Autodesk Fusion 360 part; units mm, degrees
(part 2 of 2)
equation "d1675 = ( lt_x + pk_h ) - ( lt_x - pk_h )"
equation "d1676 = ( y_bg + rt_h ) - ( y_bg - rt_h )"
equation "d1677 = abs(lt_x - pk_h)"
equation "d1678 = abs(y_bg - rt_h)"
equation "d1679 = ( shelf_z - 60 mm ) * ( 1 )"
equation "d1680 = ( shelf_z + 40 mm ) - ( shelf_z - 60 mm )"
equation "d1683 = abs(lt_x)"
equation "d1684 = abs(shelf_z)"
equation "d1685 = ( y_bf ) * ( 1 )"
equation "d1686 = ( y_bf + tray_t + felt_t ) - ( y_bf )"
equation "d1688 = ( cut_x1 + tray_t + pk_l ) - ( cut_x1 + tray_t )"
equation "d1689 = ( y_bg + rt_h ) - ( y_bg - rt_h )"
equation "d1690 = abs(cut_x1 + tray_t)"
equation "d1691 = abs(y_bg - rt_h)"
equation "d1692 = ( trunk_z - pk_h ) * ( 1 )"
equation "d1693 = ( trunk_z + pk_h ) - ( trunk_z - pk_h )"
equation "d1695 = ( x_rf - tray_t - grm_c ) - ( cut_x1 + tray_t + pk_l )"
equation "d1696 = ( y_bg + rt_h ) - ( y_bg - rt_h )"
equation "d1697 = abs(cut_x1 + tray_t + pk_l)"
equation "d1698 = abs(y_bg - rt_h)"
equation "d1699 = ( trunk_z - rt_w / 2 ) * ( 1 )"
equation "d1700 = ( trunk_z + rt_w / 2 ) - ( trunk_z - rt_w / 2 )"
equation "d1702 = ( x_rf + tray_t + felt_t ) - ( x_rf )"
equation "d1703 = ( y_bf + 20 mm ) - ( y_bf + 2 mm )"
equation "d1704 = abs(x_rf)"
equation "d1705 = abs(y_bf + 2 mm)"
equation "d1706 = ( trunk_z - 60 mm ) * ( 1 )"
equation "d1707 = ( trunk_z + 60 mm ) - ( trunk_z - 60 mm )"
equation "d1709 = ( x_rg + rt_h ) - ( x_rg - rt_h )"
equation "d1710 = ( y_xc + cs_h ) - ( y_xc + cs_h - pk_l )"
equation "d1711 = abs(x_rg - rt_h)"
equation "d1712 = abs(y_xc + cs_h - pk_l)"
equation "d1713 = ( trunk_z - pk_h ) * ( 1 )"
equation "d1714 = ( trunk_z + pk_h ) - ( trunk_z - pk_h )"
equation "d1716 = ( x_rf ) - ( x_rf - tray_t - grm_c )"
equation "d1717 = ( y_xc + cs_h ) - ( y_xc - cs_h )"
equation "d1718 = abs(x_rf - tray_t - grm_c)"
equation "d1719 = abs(y_xc - cs_h)"
equation "d1720 = ( trunk_z - 40 mm ) * ( 1 )"
equation "d1721 = ( trunk_z + 40 mm ) - ( trunk_z - 40 mm )"
equation "d1723 = ( x_rg + rt_h ) - ( x_rg - rt_h )"
equation "d1724 = ( y_xc + cs_h - pk_l ) - ( y_kit + pk_l / 2 )"
equation "d1725 = abs(x_rg - rt_h)"
equation "d1726 = abs(y_kit + pk_l / 2)"
equation "d1727 = ( trunk_z - rt_w / 2 ) * ( 1 )"
equation "d1728 = ( trunk_z + rt_w / 2 ) - ( trunk_z - rt_w / 2 )"
equation "d1730 = ( x_rg + rt_h ) - ( x_rg - rt_h )"
equation "d1731 = ( y_kit + pk_l / 2 ) - ( y_kit - pk_l / 2 )"
equation "d1732 = abs(x_rg - rt_h)"
equation "d1733 = abs(y_kit - pk_l / 2)"
equation "d1734 = ( trunk_z - rt_w / 2 ) * ( 1 )"
equation "d1735 = ( trunk_z + rt_w / 2 + 120 mm ) - ( trunk_z - rt_w / 2 )"
equation "d1737 = kit_d"
equation "d1738 = abs(y_kit)"
equation "d1739 = abs(trunk_z + 80 mm)"
equation "d1740 = ( x_rf ) * ( 1 )"
equation "d1741 = ( x_rf + tray_t + felt_t ) - ( x_rf )"
equation "d1743 = ( x_rg + rt_h ) - ( x_rg - rt_h )"
equation "d1744 = ( y_kit - pk_l / 2 ) - ( y_cx - grm_d / 2 )"
equation "d1745 = abs(x_rg - rt_h)"
equation "d1746 = abs(y_cx - grm_d / 2)"
equation "d1747 = ( trunk_z - rt_w / 2 ) * ( 1 )"
equation "d1748 = ( trunk_z + rt_w / 2 ) - ( trunk_z - rt_w / 2 )"
equation "d1750 = grm_d"
equation "d1751 = abs(y_cx)"
equation "d1752 = abs(trunk_z)"
equation "d1753 = ( x_rf - ch_off ) * ( 1 )"
equation "d1754 = ( x_rf + tray_t + felt_t ) - ( x_rf - ch_off )"
equation "d1756 = ( x_rf - ch_off ) - ( x_rf - ch_off - ch_w )"
equation "d1757 = ( col_y1 - col_skin ) - ( col_y1 - col_skin - ch_w )"
equation "d1758 = abs(x_rf - ch_off - ch_w)"
equation "d1759 = abs(col_y1 - col_skin - ch_w)"
equation "d1760 = ( trunk_z - grm_d ) * ( 1 )"
equation "d1761 = ( col_z1 - grm_c ) - ( trunk_z - grm_d )"
equation "d1763 = ( x_rf - ch_off ) - ( x_rf - ch_off - ch_w )"
equation "d1764 = ( col_y1 - col_skin - ch_w ) - ( col_y0 + grm_c )"
equation "d1765 = abs(x_rf - ch_off - ch_w)"
equation "d1766 = abs(col_y0 + grm_c)"
equation "d1767 = ( col_z1 - 20 mm ) * ( 1 )"
equation "d1768 = ( col_z1 - 4 mm ) - ( col_z1 - 20 mm )"
equation "d1770 = grm_d"
equation "d1771 = abs(x_rf - ch_off - ch_w / 2)"
equation "d1772 = abs(col_z1 - 12 mm)"
equation "d1773 = ( col_y0 - grm_c ) * ( 1 )"
equation "d1774 = ( col_y0 + grm_c ) - ( col_y0 - grm_c )"
equation "d1776 = ( x_rf - ch_off ) - ( x_rf - ch_off - ch_w )"
equation "d1777 = ( col_y0 - grm_c ) - ( col_y0 - 20 mm )"
equation "d1778 = abs(x_rf - ch_off - ch_w)"
equation "d1779 = abs(col_y0 - 20 mm)"
equation "d1780 = ( col_z1 - 20 mm ) * ( 1 )"
equation "d1781 = ( col_z1 - 4 mm ) - ( col_z1 - 20 mm )"
equation "d1783 = grm_d"
equation "d1784 = abs(x_rf - ch_off - ch_w / 2)"
equation "d1785 = abs(col_y1 - col_skin - ch_w / 2)"
equation "d1786 = ( col_z1 - grm_c ) * ( 1 )"
equation "d1787 = ( col_z1 + grm_c ) - ( col_z1 - grm_c )"
equation "d1789 = ( x_rf - ch_off ) - ( x_rf - ch_off - ch_w )"
equation "d1790 = ( col_y1 - col_skin ) - ( col_y1 - col_skin - ch_w )"
equation "d1791 = abs(x_rf - ch_off - ch_w)"
equation "d1792 = abs(col_y1 - col_skin - ch_w)"
equation "d1793 = ( col_z1 + grm_c ) * ( 1 )"
equation "d1794 = ( col_z1 + 40 mm ) - ( col_z1 + grm_c )"
equation "d1796 = ( hub_x0 + hub_w ) - ( hub_x0 )"
equation "d1797 = ( col_y1 ) - ( col_y1 - hub_rec )"
equation "d1798 = abs(hub_x0)"
equation "d1799 = abs(col_y1 - hub_rec)"
equation "d1800 = ( hub_zc - hub_w / 2 ) * ( 1 )"
equation "d1801 = ( hub_zc + hub_w / 2 ) - ( hub_zc - hub_w / 2 )"
equation "d1803 = grm_s"
equation "d1804 = abs(call_y)"
equation "d1805 = abs(shelf_z)"
equation "d1806 = ( x_rf ) * ( 1 )"
equation "d1807 = ( x_rf + tray_t + felt_t ) - ( x_rf )"
equation "d1809 = ( x_rg + rt_h ) - ( x_rg - rt_h )"
equation "d1810 = ( call_y + pk_h ) - ( call_y - pk_h )"
equation "d1811 = abs(x_rg - rt_h)"
equation "d1812 = abs(call_y - pk_h)"
equation "d1813 = ( shelf_z - grm_s / 2 - pk_l ) * ( 1 )"
equation "d1814 = ( shelf_z - grm_s / 2 ) - ( shelf_z - grm_s / 2 - pk_l )"
equation "d1816 = ( x_rg + rt_h ) - ( x_rg - rt_h )"
equation "d1817 = ( call_y + rt_h ) - ( call_y - rt_h )"
equation "d1818 = abs(x_rg - rt_h)"
equation "d1819 = abs(call_y - rt_h)"
equation "d1820 = ( call_z + grm_s / 2 ) * ( 1 )"
equation "d1821 = ( shelf_z - grm_s / 2 - pk_l ) - ( call_z + grm_s / 2 )"
equation "d1823 = grm_s"
equation "d1824 = abs(call_y)"
equation "d1825 = abs(call_z)"
equation "d1826 = ( x_rf ) * ( 1 )"
equation "d1827 = ( x_rf + tray_t + felt_t ) - ( x_rf )"
equation "d1829 = ( lt_x + dw_h ) - ( lt_x - dw_h )"
equation "d1830 = ( y_bg + dw_h ) - ( y_bg - dw_h )"
equation "d1831 = abs(lt_x - dw_h)"
equation "d1832 = abs(y_bg - dw_h)"
equation "d1833 = ( shelf_z + 40 mm ) * ( 1 )"
equation "d1834 = ( z_cf - 4 mm ) - ( shelf_z + 40 mm )"
equation "d1836 = ( ceil_x + dw_h ) - ( lt_x - dw_h )"
equation "d1837 = ( y_bg + dw_h ) - ( y_bg - dw_h )"
equation "d1838 = abs(lt_x - dw_h)"
equation "d1839 = abs(y_bg - dw_h)"
equation "d1840 = ( z_cf - 4 mm ) * ( 1 )"
equation "d1841 = ( z_cf + 4 mm ) - ( z_cf - 4 mm )"
equation "d1843 = ( ceil_x + dw_h ) - ( ceil_x - dw_h )"
equation "d1844 = ( y_bg + dw_h ) - ( y_bg - dw_h )"
equation "d1845 = abs(ceil_x - dw_h)"
equation "d1846 = abs(y_bg - dw_h)"
equation "d1847 = ( z_cf + 4 mm ) * ( 1 )"
equation "d1848 = ( z_xc + dw_h ) - ( z_cf + 4 mm )"
equation "d1850 = grm_s"
equation "d1851 = abs(ceil_x)"
equation "d1852 = abs(z_xc)"
equation "d1853 = ( y_bf ) * ( 1 )"
equation "d1854 = ( y_bf + tray_t + felt_t ) - ( y_bf )"
equation "d1856 = grm_d"
equation "d1857 = abs(ceil_x)"
equation "d1858 = abs(z_xc)"
equation "d1859 = ( ceil_y1 - tray_t ) * ( 1 )"
equation "d1860 = ( y_bf ) - ( ceil_y1 - tray_t )"
equation "d1862 = ( ceil_x + dw_h ) - ( ceil_x - dw_h )"
equation "d1863 = ( ceil_y1 - tray_t ) - ( ceil_y0 + tray_t )"
equation "d1864 = abs(ceil_x - dw_h)"
equation "d1865 = abs(ceil_y0 + tray_t)"
equation "d1866 = ( z_xc - dw_h ) * ( 1 )"
equation "d1867 = ( z_cg + dw_h ) - ( z_xc - dw_h )"
equation "d1869 = grm_d"
equation "d1870 = abs(ceil_x)"
equation "d1871 = abs(z_cg)"
equation "d1872 = ( soff_y ) * ( 1 )"
equation "d1873 = ( ceil_y0 + tray_t ) - ( soff_y )"
named bodies: "PU POWER UNIT ENVELOPE", "PU-PLATE FRONT PLATE - OVER THE FELT EDGE, 2 MM OFF THE FELT", "INLET MAINS INLET ENVELOPE", "LAN-FT LAN FEED-THROUGH ENVELOPE", "SLEEVE MAINS AND LAN SLEEVE", "P5 POCKET - LIGHT FEED AT THE UNIT", "L1-B2 ROUTE - LIGHT FEED - B2-CASS", "G-B2-B4 GROMMET PAIR - B2/B4 LINING JOINT", "P4 POCKET - LIGHT FEED AT THE B2/B4 JOINT - B4-CASS", "L1-B4 ROUTE - LIGHT FEED - B4-CASS", "P6 POCKET - LIGHT SHELF FEED", "FX-SHELF FELT HOLE - LIGHT SHELF EXIT (FELT ONLY, NO STEEL)", "P1 POCKET - TRUNK AT THE UNIT", "T1-B2 ROUTE - TRUNK - B2-CASS", "FS-CNR FELT SLOT - CORNER - R1-CASS (HIDDEN BEHIND B2-CASS)", "P2 POCKET - TRUNK AT THE BACK-RIGHT CORNER - R1-CASS", "S-CNR GROMMETED SLOT - CORNER - B2-CASS END RETURN", "T1-R1A ROUTE - TRUNK - R1-CASS - CORNER TO KIT", "P3-KIT POCKET - VOICE KIT DROP", "FA-KIT FELT HOLE - VOICE KIT ACCESS (FELT ONLY, NO STEEL)", "T1-R1B ROUTE - TRUNK - R1-CASS - KIT TO COLUMN", "FX-COL FELT HOLE - EXIT INTO THE AIR COLUMN (FELT ONLY, NO STEEL)", "CHASE ROUTE - CABLE CHASE IN THE AIR COLUMN", "TO-DR ROUTE - ACROSS THE COLUMN TOP TO DR", "G-DR BUSHED HOLE - DR BACK PLATE", "IN-DR ROUTE - INSIDE DR TO THE SUPPLY FAN BOX AND INLET SENSOR", "G-SOFFIT BUSHED HOLE - SOFFIT UNDERSIDE CASING", "TO-SOFFIT ROUTE - TO THE EXHAUST FANS IN THE SOFFIT", "HUB SENSOR HUB AND CONTROLS ZONE", "FX-CALL0 FELT HOLE - R2-CASS BEHIND THE SHELF (FELT ONLY, NO STEEL)", "P7 POCKET - CALL LIGHT DROP AT THE SHELF - R2-CASS", "CALL-R2 ROUTE - CALL LIGHT DROP - R2-CASS", "FX-CALL2 FELT HOLE - CALL LIGHT EXIT (FELT ONLY, NO STEEL)", "C1-UP DRAW WIRE - B4-CASS UP", "C1-JOG DRAW WIRE - B4-CASS ALONG X", "C1-RISE DRAW WIRE - B4-CASS TO THE CEILING HOLE", "FX-CEIL FELT HOLE - B4-CASS BELOW ITS TOP LIP (FELT ONLY, NO STEEL)", "G-CEIL-B GROMMET - CEILING CASSETTE BACK RETURN", "C1-CEIL DRAW WIRE - CEILING CASSETTE", "G-CEIL-F GROMMET - CEILING CASSETTE FRONT RETURN"
